PowerSupply (Autodesk Fusion 360 design; units mm, degrees)
part number: 2026-04-29-23-24-09-066
Autodesk Fusion 360 part; units mm, degrees
sketch "Sketch1" plane through (0, 0, 0) normal (0, 0, 1) x (1, 0, 0)
  line L0 (-100, 64) -> (100, 64)
  line L1 (100, 64) -> (100, -64)
  line L2 (100, -64) -> (-100, -64)
  line L3 (-100, -64) -> (-100, 64)
  line L4 (0, 1.75) -> (0, 22.5)
  line L5 (1.75, 0) -> (22.5, 0)
  circle A0 centre (95.5, 60) radius 1.75
  circle A1 centre (95.5, -60) radius 1.75
  circle A2 centre (-95.5, 60) radius 1.75
  circle A3 centre (-95.5, -60) radius 1.75
  dimension "d1" = 200
  dimension "d2" = 128
  dimension "d3" = 3.5
  dimension "d5" = 3.5
  dimension "d6" = 3.5
  dimension "d13" = 3.5
  dimension "d25" = 120
  dimension "d26" = 191
  dimension "d27" = 120
  constraint horizontal L0
  constraint vertical L1
  constraint horizontal L2
  constraint vertical L3
  constraint symmetric L1 L3 L4
  constraint symmetric L0 L2 L5
  constraint symmetric L5 A2.centre A3.centre
  constraint symmetric L4 A0.centre A2.centre
  constraint symmetric L5 A0.centre A1.centre
  measures "d1" distance of L0.start L0.end
  measures "d2" distance of L0.end L1.end
  measures "d3" diameter of A0
  measures "d5" diameter of A1
  measures "d6" diameter of A2
  measures "d13" diameter of A3
  measures "d25" distance of A2.centre A3.centre
  measures "d26" distance of A0.centre A2.centre
  measures "d27" distance of A0.centre A1.centre
extrude "Extrude1" add sketch "Sketch1" along normal blind 2
sketch "Sketch2" plane through (0, 0, 2) normal (0, 0, 1) x (-1, 0, 0)
  circle A0 centre (-95.5, 60) radius 1.75
  circle A1 centre (95.5, -60) radius 1.75
  circle A2 centre (95.5, 60) radius 1.75
  circle A3 centre (-95.5, -60) radius 1.75
  line L0 (100, 64) -> (-100, 64)
  line L1 (-100, 64) -> (-100, -64)
  line L2 (-100, -64) -> (100, -64)
  line L3 (100, -64) -> (100, 64)
  line L4 (76.3678, 34.7438) -> (-90.4182, 34.7438)
  line L5 (-90.4182, 34.7438) -> (-90.4182, 63.5854)
  line L6 (-90.4182, 63.5854) -> (76.3678, 63.5854)
  line L7 (76.3678, 63.5854) -> (76.3678, 34.7438)
  line L8 (25.9039, -32.9223) -> (-27.1804, -32.9223)
  line L9 (-27.1804, -32.9223) -> (-27.1804, 23.2346)
  line L10 (-27.1804, 23.2346) -> (25.9039, 23.2346)
  line L11 (25.9039, 23.2346) -> (25.9039, -32.9223)
  circle A4 centre (-40.1469, -47.7985) radius 15.8509
  circle A5 centre (-76.5258, -48.3834) radius 15
  dimension "d18" = 30
  constraint horizontal L4
  constraint vertical L5
  constraint horizontal L6
  constraint vertical L7
  constraint horizontal L8
  constraint vertical L9
  constraint horizontal L10
  constraint vertical L11
  measures "d18" diameter of A5
extrude "Extrude2" add sketch "Sketch2" along normal blind 60 contours L8 L9 L10 L11
extrude "Extrude3" add sketch "Sketch2" along normal blind 40 contours A4 | A5
extrude "Extrude4" add sketch "Sketch2" along normal blind 50 contours L4 L5 L6 L7
